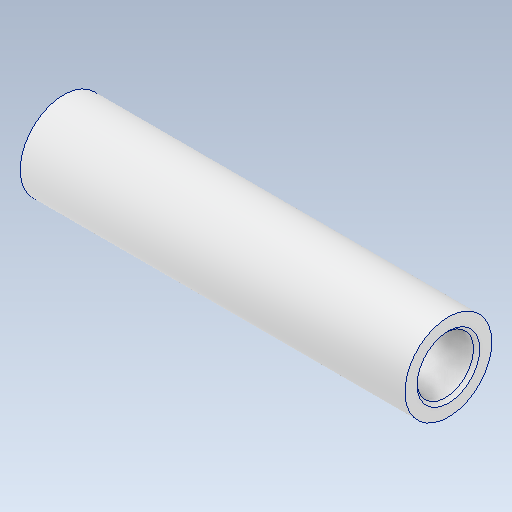
# Autodesk Inventor part: 1.1_7_SpacerB
Saved by Autodesk Inventor 2021 (Build 250183000, 183)
## iProperties
Created: 2025-11-22
Part Number: 1.1_7_SpacerB
Material: Aluminum 6061
Document SubType Name: Modeling
Designer: Admin
Density: 2.7 g/cm^3
Appearance: Aluminum - Flat
Author: Admin
Autodesk Inventor part; units mm, degrees
ref_plane "YZ Plane" through (0, 0, 0) normal (1, 0, 0) x (0, 1, 0)
ref_plane "XZ Plane" through (0, 0, 0) normal (0, 1, 0) x (-1, 0, 0)
ref_plane "XY Plane" through (0, 0, 0) normal (0, 0, 1) x (1, 0, 0)
sketch "Sketch1" plane through (0, 0, 0) normal (0, 1, 0) x (-1, 0, 0)
  line L0 (0, -4.55) -> (-62, -4.55)
  line L1 (-62, -4.55) -> (-62, -7)
  line L2 (-62, -7) -> (0, -7)
  line L3 (0, -7) -> (0, -4.55)
  line L4 (0, -8.4) -> (0, 1.4) projected
  line L5 (-74.4, 0) -> (12.4, 0) projected
  point P0 (0, 0)
  dimension "d0" = 4.55
  dimension "d1" = 7
  dimension "d2" = 62
  constraints: 8 end point, 3 perpendicular, 1 collinear, 1 horizontal
  measures "d0" distance between parallel lines of L5 L0
  measures "d1" distance between parallel lines of L5 L2
  measures "d2" distance of L1.end L2.end
revolve "Revolution1" add sketch "Sketch1" angle 360 about axis through (0, 0, 0) along (-1, 0, 0)
chamfer "Chamfer1" distance 0.5 angle 45 2 edges at (0, 0, 4.55) (62, 0, 4.55)
body "Solid1"
